Display (Autodesk Fusion 360 design; units mm, degrees)
part number: 2026-04-30-01-18-59-019
Autodesk Fusion 360 part; units mm, degrees
sketch "Sketch1" plane through (0, 0, 0) normal (0, 0, 1) x (1, 0, 0)
  line L0 (-39, 22) -> (39, 22)
  line L1 (39, 22) -> (39, -22)
  line L2 (39, -22) -> (-39, -22)
  line L3 (-39, -22) -> (-39, 22)
  line L4 (1.75, 0) -> (22.5, 0)
  line L5 (0, 1.75) -> (0, 22.5)
  dimension "d1" = 78
  dimension "d2" = 44
  constraint horizontal L0
  constraint vertical L1
  constraint horizontal L2
  constraint vertical L3
  constraint symmetric L0 L2 L4
  constraint symmetric L1 L3 L5
  measures "d1" distance of L0.start L0.end
  measures "d2" distance of L0.end L1.end
extrude "Extrude1" add sketch "Sketch1" along normal blind 23
sketch "Sketch2" plane through (0, 0, 23) normal (0, 0, 1) x (-1, 0, 0)
  line L0 (39, 22) -> (-39, 22)
  line L1 (-39, 22) -> (-39, -22)
  line L2 (-39, -22) -> (39, -22)
  line L3 (39, -22) -> (39, 22)
  line L4 (40, -24) -> (-40, -24)
  line L5 (-41.5, -22.5) -> (-41.5, 22.5)
  line L6 (-40, 24) -> (40, 24)
  line L7 (41.5, 22.5) -> (41.5, -22.5)
  line L8 (0, -1.75) -> (0, -22.5)
  line L9 (-1.75, 0) -> (-22.5, 0)
  arc A0 (-41.5, -22.5) -> (-40, -24) centre (-40, -22.5) ccw
  arc A1 (-40, 24) -> (-41.5, 22.5) centre (-40, 22.5) ccw
  arc A2 (40, -24) -> (41.5, -22.5) centre (40, -22.5) ccw
  arc A3 (41.5, 22.5) -> (40, 24) centre (40, 22.5) ccw
  point P0 (41.5, -24)
  point P1 (-41.5, -24)
  point P2 (41.5, 24)
  dimension "d5" = 83
  dimension "d6" = 48
  dimension "d7" = 1.5
  constraint horizontal L4
  constraint vertical L5
  constraint horizontal L6
  constraint vertical L7
  constraint symmetric L5 L7 L8
  constraint symmetric L4 L6 L9
  constraint coincident P1 L4
  constraint coincident P1 L5
  constraint tangent L4 A0
  constraint tangent L5 A0
  constraint tangent L5 A1
  constraint tangent L6 A1
  constraint equal A0 A1
  constraint coincident P0 L4
  constraint coincident P0 L7
  constraint tangent L4 A2
  constraint tangent L7 A2
  constraint equal A0 A2
  constraint coincident P2 L6
  constraint coincident P2 L7
  constraint tangent L6 A3
  constraint tangent L7 A3
  constraint equal A0 A3
  measures "d5" distance of P0 P1
  measures "d6" distance of P0 P2
  measures "d7" radius of A0
extrude "Extrude2" add sketch "Sketch2" along normal blind 2 contours L0 L1 L2 L3 | L4 L5 L6 L7 A0 A1 A2 A3
sketch "Sketch3" plane through (-39, 0, 0) normal (-1, 0, 0) x (0, -1, 0)
  line L0 (-22, 0) -> (22, 0)
  line L1 (22, 0) -> (22, 23)
  line L2 (22, 23) -> (-22, 23)
  line L3 (-22, 23) -> (-22, 0)
  line L4 (-6, 23) -> (6, 23)
  line L5 (6, 23) -> (6, 12)
  line L6 (6, 12) -> (-6, 12)
  line L7 (-6, 12) -> (-6, 23)
  line L8 (0, 1.75) -> (0, 22.5)
  dimension "d10" = 12
  dimension "d11" = 11
  constraint horizontal L4
  constraint vertical L5
  constraint horizontal L6
  constraint vertical L7
  constraint coincident L2 L4.start
  constraint symmetric L5 L7 L8
  measures "d10" distance of L4.start L4.end
  measures "d11" distance of L4.end L5.end
extrude "Extrude3" add sketch "Sketch3" along normal blind 1.5 contours L2 L4 L5 L6 L7
sketch "Sketch4" plane through (39, 0, 0) normal (1, 0, 0) x (0, 1, 0)
  line L0 (-22, 0) -> (22, 0)
  line L1 (22, 0) -> (22, 23)
  line L2 (22, 23) -> (-22, 23)
  line L3 (-22, 23) -> (-22, 0)
  line L4 (6, 23) -> (-6, 23)
  line L5 (-6, 23) -> (-6, 12)
  line L6 (-6, 12) -> (6, 12)
  line L7 (6, 12) -> (6, 23)
  constraint horizontal L4
  constraint vertical L5
  constraint horizontal L6
  constraint vertical L7
  constraint coincident L2 L4.start
extrude "Extrude4" add sketch "Sketch4" along normal blind 1.5 contours L2 L4 L5 L6 L7
